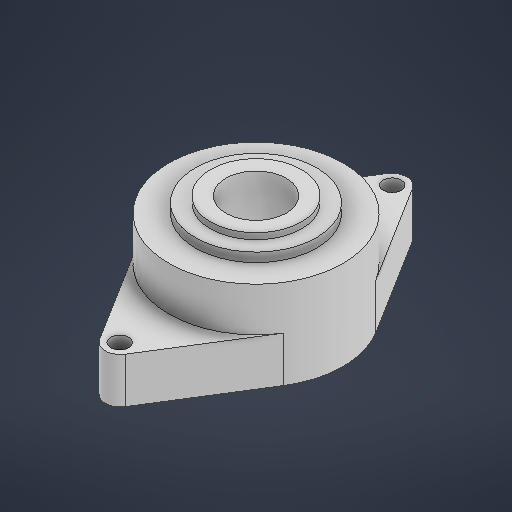
# Autodesk Inventor part: bearing
Saved by Autodesk Inventor 2026.1 (Build 301233000, 233)
## iProperties
Created: 2025-11-11
Part Number: bearing
Material: Generic
Document SubType Name: Modeling
Designer: shiva
Density: 1 g/cm^3
Appearance: Default
Author: shiva
Autodesk Inventor part; units mm, degrees
ref_plane "YZ Plane" through (0, 0, 0) normal (1, 0, 0) x (0, 1, 0)
ref_plane "XZ Plane" through (0, 0, 0) normal (0, 1, 0) x (-1, 0, 0)
ref_plane "XY Plane" through (0, 0, 0) normal (0, 0, 1) x (1, 0, 0)
sketch "Sketch1" plane through (0, 0, 0) normal (0, 1, 0) x (-1, 0, 0)
  circle A0 centre (0, 0) radius 10
  line L0 (0, 45) -> (0, -45)
  line L1 (0, 45) -> (90, 45) construction
  circle A1 centre (0, -45) radius 3
  circle A2 centre (0, 45) radius 3
  line L2 (0, 45) -> (0, 54.25)
  line L3 (0, -45) -> (0, -54.25)
  line L4 (4.2401, 47.465) -> (24.3808, 15.2362)
  line L5 (-4.2401, 47.465) -> (-24.3808, 15.2362)
  line L6 (4.2401, -47.465) -> (24.3808, -15.2362)
  line L7 (-4.2401, -47.465) -> (-24.3808, -15.2362)
  arc A3 (4.2401, 47.465) -> (-4.2401, 47.465) centre (0, 44.8152) ccw
  arc A4 (-4.2401, -47.465) -> (4.2401, -47.465) centre (0, -44.8152) ccw
  arc A5 (-24.3808, 15.2362) -> (-24.3808, -15.2362) centre (0, 0) ccw
  arc A6 (24.3808, -15.2362) -> (24.3808, 15.2362) centre (0, 0) ccw
  dimension "d0" = 20
  dimension "d1" = 90
  dimension "d2" = 90
  dimension "d3" = 6
  dimension "d4" = 6
  dimension "d5" = 9.25
  dimension "d6" = 9.25
  dimension "d8" = 5
  constraints: 16 end point, 8 point on circle, 7 centre point, 5 tangent, 4 coincident, 4 point on line, 3 vertical, 1 equal radius, 1 horizontal, 1 midpoint, 1 perpendicular, 1 symmetric about line
  measures "d0" diameter of A0
  measures "d1" distance of L0.start L0.end
  measures "d2" angle of L0 L1
  measures "d3" diameter of A1
  measures "d4" diameter of A2
  measures "d5" distance of L2.start L2.end
  measures "d6" distance of L3.start L3.end
  measures "d8" radius of A3
extrude "Extrusion1" add sketch "Sketch1" along normal blind 15 contours A0 L0 A2 L2 A3 L4 A6 L6 A4 L3 A1 | A0 L0 A1 L3 A4 L7 A5 L5 A3 L2 A2
sketch "Sketch2" plane through (0, 15, 0) normal (0, 1, 0) x (1, 0, 0)
  circle A0 centre (0, 0) radius 28.75
  circle A1 centre (0, 0) radius 10
  dimension "d11" = 57.5
  dimension "d14" = 20
  constraints: 2 centre point, 2 coincident
  measures "d11" diameter of A0
  measures "d14" diameter of A1
extrude "Extrusion2" add sketch "Sketch2" along normal blind 14.5
sketch "Sketch3" plane through (0, 29.5, 0) normal (0, 1, 0) x (1, 0, 0)
  circle A0 centre (0, 0) radius 10
  circle A1 centre (0, 0) radius 15
  dimension "d15" = 30
  constraints: 2 centre point, 2 coincident
  measures "d15" diameter of A1
extrude "Extrusion3" add sketch "Sketch3" along normal blind 5
sketch "Sketch4" plane through (0, 29.5, 0) normal (0, 1, 0) x (1, 0, 0)
  circle A0 centre (0, 0) radius 15
  circle A1 centre (0, 0) radius 20
  dimension "d18" = 40
  constraints: 2 centre point, 2 coincident
  measures "d18" diameter of A1
extrude "Extrusion4" add sketch "Sketch4" along normal blind 3
body "Solid1"
